Battery body post holder (Autodesk Fusion 360 design; units mm, degrees)
Autodesk Fusion 360 part; units mm, degrees
sketch "Sketch1" plane through (0, 0, 0) normal (0, 1, 0) x (1, 0, 0)
  circle A0 centre (0, 0) radius 3.25
  dimension "d1" = 6.5
  constraint coincident A0.centre origin
  measures "d1" diameter of A0
extrude "Extrude1" add sketch "Sketch1" along normal blind 22
ref_plane "WorkPlane1" through (-3.2477, 13.9049, 0.1226) normal (-0.999288, 0, 0.037717) x (-0.037717, 0, -0.999288)
sketch "Sketch2" plane through (-3.2477, 13.9049, 0.1226) normal (-0.999288, 0, 0.037717) x (-0.037717, 0, -0.999288)
  line L0 (-3.25, -8.0951) -> (3.25, -8.0951)
  line L1 (0, -8.0951) -> (0, -5.9951) construction
  circle A0 centre (0, -5.9951) radius 2.1
  line L2 (0, -5.9951) -> (6.2036, -5.9951) construction
  line L3 (0, -5.9951) -> (-6.1712, -5.9951) construction
  line L4 (0, -5.9951) -> (0, -2.754) construction
  line L5 (0, -3.8951) -> (0, -2.8951)
  line L6 (0, -2.8951) -> (-0.25, -2.8951)
  line L7 (0, -2.8951) -> (0.25, -2.8951)
  line L8 (0.25, -2.8951) -> (0.25, -3.91)
  line L9 (-0.25, -2.8951) -> (-0.25, -3.91)
  line L10 (0, -3.8951) -> (0, -3.3951)
  arc A1 (0.25, -3.4025) -> (0, -2.8951) centre (-0.336, -3.3759) ccw
  arc A2 (0, -2.8951) -> (-0.25, -3.4025) centre (0.3147, -3.3654) ccw
  line L11 (2.1, -5.9951) -> (1.0627, -8.2195)
  line L12 (2.1, -5.9951) -> (4.5544, -5.9951) construction
  line L13 (-2.1, -5.9951) -> (-0.9628, -8.4338)
  line L14 (-2.1, -5.9951) -> (0.5908, -5.9951) construction
  line L15 (0.25, -3.4025) -> (0.4207, -4.0395)
  line L16 (0.25, -3.4025) -> (0.9094, -3.4025) construction
  line L17 (-0.25, -3.4025) -> (-0.4484, -4.1428)
  line L18 (-0.25, -3.4025) -> (0.5164, -3.4025) construction
  arc A3 (0.25, -3.4025) -> (0.3919, -3.9319) centre (1.3088, -3.4025) ccw
  arc A4 (-0.3919, -3.9319) -> (-0.25, -3.4025) centre (-1.3088, -3.4025) ccw
  dimension "d5" = 2.1
  dimension "d6" = 4.2
  dimension "d7" = 1
  dimension "d8" = 0.25
  dimension "d9" = 0.25
  dimension "d10" = 115
  dimension "d11" = 65
  dimension "d12" = 75
  dimension "d13" = 105
  constraint midpoint L0 L1.start
  constraint coincident L1.end A0.centre
  constraint perpendicular L1 L2
  constraint perpendicular L1 L3
  constraint perpendicular L3 L4
  constraint coincident A0 L5.start
  constraint coincident L4 L5.start
  constraint coincident A0 L8.end
  constraint perpendicular L7 L8
  constraint coincident A0 L9.end
  constraint perpendicular L6 L9
  constraint midpoint L5 L10.end
  constraint midpoint L8 A1.start
  constraint midpoint L9 A2.end
  constraint coincident A0 L11.start
  constraint coincident L2 L11.start
  constraint horizontal L12
  constraint coincident A0 L13.start
  constraint coincident L3 L13.start
  constraint horizontal L14
  constraint horizontal L16
  constraint horizontal L18
  constraint tangent L8 A3
  constraint coincident A0 A3.end
  constraint coincident L15 A3.end
  constraint tangent L9 A4
  constraint coincident A0 A4.start
  constraint coincident L17 A4.start
  measures "d5" distance of L1.start L1.end
  measures "d6" diameter of A0
  measures "d7" distance of L5.start L5.end
  measures "d8" distance of L5.end L6.end
  measures "d9" distance of L5.end L7.end
  measures "d10" angle of L11 L12
  measures "d11" angle of L13 L14
  measures "d12" angle of L15 L16
  measures "d13" angle of L17 L18
extrude "Extrude2" cut sketch "Sketch2" against normal blind 8 contours L0 A0 L13 | L0 A0 L11 | A0 L11 L13 | A0 L13 | A0 L11 | A0 L9 A4 | A0 L8 A3 | A0 L5 L9 L10 A2 | A0 L5 L8 L10 A1
fillet "Fillet1" radius 0.25 2 edges at (-0.0423, 22, -1.12) (0.0423, 22, 1.12)
fillet "Fillet2" radius 0.1 1 edges at (0, 16.8, 0)
fillet "Fillet3" radius 0.45 2 edges at (-0.0148, 17.8369, -0.3916) (0.0148, 17.8369, 0.3916)
sketch "Sketch3" plane through (0, 0, 0) normal (0, -1, 0) x (1, 0, 0)
  circle A0 centre (0, 0) radius 3.25
  circle A1 centre (0, 0) radius 1.5
  dimension "d19" = 3
  constraint concentric A0 A1
  measures "d19" diameter of A1
extrude "Extrude3" cut sketch "Sketch3" against normal blind 0.75 contours A1
fillet "Fillet4" radius 1.5 1 edges at (-1.3985, 0.75, 0.5424)
sketch "Sketch4" plane through (0, 0.75, 0) normal (0, -1, 0) x (1, 0, 0)
  circle A0 centre (0, 0) radius 0.201
extrude "Extrude4" cut sketch "Sketch4" against normal blind 0.25
